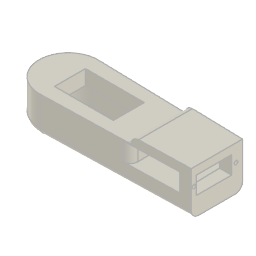
arm (Autodesk Fusion 360 design; units mm, degrees)
Autodesk Fusion 360 part; units mm, degrees
sketch "Sketch1" plane through (0, 0, 0) normal (0, 0, 1) x (1, 0, 0)
  arc A0 (0, 20) -> (0, -20) centre (-1, 0) ccw
  line L0 (0, -15) -> (40, -15)
  arc A1 (40, -15) -> (40, 15) centre (40, 0) ccw
  line L1 (40, 15) -> (0, 15)
  arc A2 (0, 15) -> (0, -15) centre (0, 0) ccw
  line L2 (0, 0) -> (40, 0) construction
  line L3 (60, 18.5) -> (60, -18.839)
  line L4 (100, 17.5) -> (100, -17.5)
  line L5 (0, -20) -> (100, -17.5)
  line L6 (0, 20) -> (100, 17.5)
  dimension "d127" = 40
  dimension "d132" = 15
  dimension "d133" = 40
  dimension "d172" = 35
  constraint coincident A2.centre L2.start
  constraint tangent L0 A1
  constraint tangent A1 L1
  constraint parallel L0 L1
  constraint tangent L1 A2
  constraint tangent L0 A2
  constraint horizontal L2
  constraint vertical L3
  constraint coincident L6 L3.start
  measures "d127" distance of A0.start A0.end
  measures "d132" radius of A2
  measures "d133" distance of A2.centre A1.centre
  measures "d172" distance of L4.start L4.end
extrude "Extrude1" add sketch "Sketch1" along normal blind 30 contours A0 L3 L5 L6 | L3 L4 L5 L6 | L0 A1 L1 A2
extrude "Extrude2" cut sketch "Sketch1" along normal blind 15 contours L0 A1 L1 A2
sketch "Sketch2" plane through (0, 0, 30) normal (0, 0, 1) x (-1, 0, 0)
  arc A0 (0, -20) -> (0, 20) centre (1, 0) ccw
  line L0 (-60, -18.5) -> (-60, 18.839)
  line L1 (0, 20) -> (-100, 17.5)
  line L2 (-100, 17.5) -> (-100, -17.5)
  line L3 (-100, -17.5) -> (0, -20)
extrude "Extrude3" cut sketch "Sketch2" against normal blind 5 contours A0 L0 L1 L3
fillet "Fillet1" radius 5 1 edges at (60, 0, 30)
fillet "Fillet1" radius 5 3 edges at (-21.025, 0, 0) (50, 18.75, 0) (50, -18.75, 0)
sketch "Sketch3" plane through (0.4997, -19.9875, 0) normal (0.024992, -0.999688, 0) x (0.999688, 0.024992, 0)
  ellipse E0 centre (64.0824, 25) end of major axis (59.0762, 25) minor radius 5 (64.0824, 30) -> (59.0762, 25) ccw
  line L0 (59.0762, 25) -> (-0.9988, 25)
  line L1 (-0.9988, 25) -> (-0.9988, 5)
  line L2 (99.1262, 5) -> (99.1262, 30)
  line L3 (99.1262, 30) -> (64.0824, 30)
  line L4 (92.0013, 12) -> (59.4151, 12)
  line L5 (59.4151, 12) -> (59.4151, 24.5)
  line L6 (59.4151, 24.5) -> (92.0013, 24.5)
  line L7 (92.0013, 24.5) -> (92.0013, 12)
  line L8 (92.0013, 12) -> (59.4151, 24.5) construction
  line L9 (59.4151, 12) -> (92.0013, 24.5) construction
  line L10 (99.0013, 5) -> (99.0013, 30)
  line L11 (-0.4998, 5) -> (99.5314, 5)
  line L12 (99.5314, 5) -> (99.5314, 30)
  line L13 (99.5314, 30) -> (64.5205, 30)
  ellipse E1 centre (64.5205, 25) end of major axis (59.5189, 25) minor radius 5 (64.5205, 30) -> (59.5189, 25) ccw
  line L14 (59.5189, 25) -> (-0.4998, 25)
  line L15 (-0.4998, 25) -> (-0.4998, 5)
  point P0 (75.7082, 18.25)
  dimension "d143" = 12.5
  dimension "d173" = 7
  constraint horizontal L4
  constraint perpendicular L4 L5
  constraint parallel L4 L6
  constraint parallel L5 L7
  constraint coincident L8 P0
  constraint coincident L9 P0
  measures "d143" distance of L4.start L6.end
  measures "d173" distance of L7 L10
extrude "Extrude4" cut sketch "Sketch3" against normal blind 55 contours L4 L5 L6 L7
sketch "Sketch4" plane through (0, 0, 15) normal (0, 0, -1) x (1, 0, 0)
  arc A0 (0, 15) -> (0, -15) centre (0, 0) ccw
  arc A1 (40, -15) -> (40, 15) centre (40, 0) ccw
  line L0 (40, 10.5) -> (0, 10.5)
  line L1 (0, 10.5) -> (0, -10.5)
  line L2 (0, -10.5) -> (40, -10.5)
  line L3 (40, -10.5) -> (40, 10.5)
  line L4 (40, 10.5) -> (0, -10.5) construction
  line L5 (0, 10.5) -> (40, -10.5) construction
  arc A2 (-0.058, 14.9999) -> (-0.058, -14.9999) centre (0, 0) ccw
  circle A3 centre (45, 5.5) radius 2.25
  circle A4 centre (-5, 5.5) radius 2.25
  line L6 (0, 0) -> (8.1722, 0) construction
  circle A5 centre (-5, -5.5) radius 2.25
  circle A6 centre (45, -5.5) radius 2.25
  point P0 (20, 0)
  point P1 (-15, 0)
  dimension "d150" = 40
  dimension "d151" = 21
  dimension "d155" = 20
  dimension "d156" = 4.5
  dimension "d157" = 4.5
  dimension "d158" = 5
  dimension "d159" = 5
  dimension "d160" = 5
  dimension "d161" = 5
  constraint horizontal L0
  constraint perpendicular L0 L1
  constraint parallel L0 L2
  constraint parallel L1 L3
  constraint coincident L4 P0
  constraint coincident L5 P0
  constraint midpoint A0 P1
  constraint coincident A0.centre A2.centre
  constraint perpendicular L1 L6
  constraint symmetric A3 L6 A6
  constraint symmetric A4 L6 A5
  measures "d150" distance of L1.end L2.end
  measures "d151" distance of L0.end L1.end
  measures "d155" distance of P0 A0.centre
  measures "d156" diameter of A3
  measures "d157" diameter of A4
  measures "d158" distance of L0 A4.centre
  measures "d159" distance of L1 A4.centre
  measures "d160" distance of L3 A3.centre
  measures "d161" distance of L0 A3.centre
extrude "Extrude5" cut sketch "Sketch4" against normal blind 23 contours L0 L1 L2 L3
extrude "Extrude6" cut sketch "Sketch4" against normal blind 5 contours A3 | A4 | A5 | A6
thread "Thread1" "ISO Metric profile 4.5 M4.5x0.75 M4.5x0.75 6H" major diameter 4.6131 minor diameter 3.7831 pitch 0.75 angle 60 resizes the face on face at (-2.7528, 5.6122, 18.3333) on face at (47.2472, 5.6122, 18.3333) on face at (47.2472, -5.3878, 18.3333) on face at (-2.7528, -5.3878, 18.3333)
sketch "Sketch5" plane through (100, 0, 0) normal (1, 0, 0) x (0, 1, 0)
  ellipse E0 centre (9.9938, 5) end of major axis (15, 5) minor radius 5 (9.9938, 0) -> (15, 5) ccw
  line L0 (15, 5) -> (15, 30)
  line L1 (15, 30) -> (-15, 30)
  line L2 (-15, 30) -> (-15, 5)
  ellipse E1 centre (-9.9938, 5) end of major axis (-15, 5) minor radius 5 (-15, 5) -> (-9.9938, 0) ccw
  line L3 (-9.9938, 0) -> (9.9938, 0)
  line L4 (10, 12.5) -> (-14, 12.5)
  line L5 (-14, 12.5) -> (-14, 24.5)
  line L6 (-14, 24.5) -> (10, 24.5)
  line L7 (10, 24.5) -> (10, 12.5)
  ellipse E2 centre (-12.4984, 5) end of major axis (-17.5, 5) minor radius 5 (-17.5, 5) -> (-12.4984, 0) ccw
  line L8 (-12.4984, 0) -> (12.4984, 0)
  ellipse E3 centre (12.4984, 5) end of major axis (17.5, 5) minor radius 5 (12.4984, 0) -> (17.5, 5) ccw
  line L9 (17.5, 5) -> (17.5, 30)
  line L10 (17.5, 30) -> (-17.5, 30)
  line L11 (-17.5, 30) -> (-17.5, 5)
  circle A0 centre (13.0177, 18.3585) radius 1.5
  circle A1 centre (-15.5, 18.5) radius 1.25
  dimension "d168" = 24
  dimension "d169" = 12
  dimension "d170" = 5
  dimension "d174" = 5.5
  dimension "d175" = 3
  dimension "d177" = 3.0177
  dimension "d237" = 1.5
  dimension "d238" = 2.5
  constraint horizontal L4
  constraint vertical L5
  constraint horizontal L6
  constraint vertical L7
  measures "d168" distance of L4.start L4.end
  measures "d169" distance of L4.start L6.end
  measures "d170" distance of L0 L7
  measures "d174" distance of L1 L6
  measures "d175" diameter of A0
  measures "d177" distance of L7 A0.centre
  measures "d237" distance of L5 A1.centre
  measures "d238" diameter of A1
extrude "Extrude7" cut sketch "Sketch5" against normal blind 10 contours L2 A1 | L2 A1 | L4 L5 L6 L7 | A0
fillet "Fillet2" radius 5 2 edges at (59.8962, -18.5026, 18.25) (58.9705, 18.5257, 18.25)
thread "Thread2" "ISO Metric profile 3.0 M3x0.5 M3x0.5 6H" major diameter 3.086 minor diameter 2.529 pitch 0.5 angle 60 resizes the face on face at (97.2266, 14.028, 19.4673) on face at (97.4622, -14.2543, 18.6036)
